room (Autodesk Fusion 360 design; units mm, degrees)
Autodesk Fusion 360 part; units mm, degrees
sketch "Sketch1" plane through (0, 0, 0) normal (0, 1, 0) x (1, 0, 0)
  line L0 (1016, -304.8) -> (-1016, -304.8)
  line L1 (-1016, -304.8) -> (-1016, 304.8)
  line L2 (-1016, 304.8) -> (1016, 304.8)
  line L3 (1016, 304.8) -> (1016, -304.8)
  line L4 (1016, -304.8) -> (-1016, 304.8) construction
  line L5 (-1016, -304.8) -> (1016, 304.8) construction
  line L6 (1016, 304.8) -> (-1016, 304.8)
  line L7 (-1016, 304.8) -> (-1016, 381)
  line L8 (-1016, 381) -> (1016, 381)
  line L9 (1016, 381) -> (1016, 304.8)
  line L10 (1016, 304.8) -> (4064, 304.8)
  line L11 (4064, 304.8) -> (4064, -609.6)
  line L12 (4064, -609.6) -> (1016, -609.6)
  line L13 (1016, -609.6) -> (1016, 304.8)
  line L14 (1016, 381) -> (4064, 381)
  line L15 (4064, 381) -> (4064, 304.8)
  line L16 (4064, 304.8) -> (1016, 304.8)
  line L17 (1016, 304.8) -> (1016, 381)
  dimension "d1" = 2032
  dimension "d2" = 609.6
  dimension "d3" = 76.2
  dimension "d4" = 914.4
  dimension "d5" = 3048
  constraint perpendicular L0 L1
  constraint parallel L0 L2
  constraint parallel L1 L3
  constraint horizontal L0
  constraint coincident L4 origin
  constraint coincident L5 origin
  constraint horizontal L6
  constraint vertical L7
  constraint horizontal L8
  constraint vertical L9
  constraint horizontal L10
  constraint vertical L11
  constraint horizontal L12
  constraint vertical L13
  constraint horizontal L14
  constraint vertical L15
  constraint horizontal L16
  constraint vertical L17
  measures "d1" distance of L1.end L2.end
  measures "d2" distance of L0.end L1.end
  measures "d3" distance of L2.end L8.end
  measures "d4" distance of L2.end L12.end
  measures "d5" distance of L2.end L10.end
extrude "Extrude1" add sketch "Sketch1" along normal blind 5080 contours L2 L6 L7 L8 L9 L17 | L9 L10 L14 L15 L16 L17 makes body 1
extrude "Extrude2" add sketch "Sketch1" along normal blind 914.4 contours L3 L10 L11 L12 L13 L16 bodies 1
sketch "Sketch2" plane through (0, 914.4, 0) normal (0, 1, 0) x (-1, 0, 0)
  line L0 (-4064, 609.6) -> (-4064, -304.8)
  line L1 (-4064, -304.8) -> (-1016, -304.8)
  line L2 (-1016, -304.8) -> (-1016, 609.6)
  line L3 (-1016, 609.6) -> (-4064, 609.6)
  line L4 (-1016, 609.6) -> (-1320.8, 609.6)
  line L5 (-1320.8, 609.6) -> (-1320.8, -304.8)
  line L6 (-1320.8, -304.8) -> (-1016, -304.8)
  line L7 (-1016, -304.8) -> (-1016, 609.6)
  line L8 (-4064, 609.6) -> (-3759.2, 609.6)
  line L9 (-3759.2, 609.6) -> (-3759.2, -304.8)
  line L10 (-3759.2, -304.8) -> (-4064, -304.8)
  line L11 (-4064, -304.8) -> (-4064, 609.6)
  line L12 (-1016, -304.8) -> (-4064, -304.8)
  line L13 (-4064, -304.8) -> (-4064, -101.6)
  line L14 (-4064, -101.6) -> (-1016, -101.6)
  line L15 (-1016, -101.6) -> (-1016, -304.8)
  dimension "d10" = 304.8
  dimension "d11" = 304.8
  dimension "d12" = 203.2
  constraint horizontal L4
  constraint vertical L5
  constraint horizontal L6
  constraint vertical L7
  constraint coincident L2.end L3.start
  constraint horizontal L8
  constraint vertical L9
  constraint horizontal L10
  constraint vertical L11
  constraint coincident L0.start L3.end
  constraint horizontal L12
  constraint vertical L13
  constraint horizontal L14
  constraint vertical L15
  measures "d10" distance of L2.end L4.end
  measures "d11" distance of L0.start L8.end
  measures "d12" distance of L1.end L14.end
extrude "Extrude3" cut sketch "Sketch2" against normal blind 609.6 contours L3 L5 L9 L14 bodies 1
extrude "Extrude4" add sketch "Sketch1" along normal blind 2032 separate body contours L0 L1 L2 L3 L6 L13 makes body 2
sketch "Sketch3" plane through (0, 0, -304.8) normal (0, 0, 1) x (1, 0, 0)
  line L0 (1016, 0) -> (1016, 914.4)
  line L1 (1016, 914.4) -> (4064, 914.4)
  line L2 (4064, 914.4) -> (4064, 5080)
  line L3 (4064, 5080) -> (-1016, 5080)
  line L4 (-1016, 5080) -> (-1016, 0)
  line L5 (-1016, 0) -> (1016, 0)
  line L6 (-1016, 0) -> (76.2, 0)
  line L7 (76.2, 0) -> (76.2, 736.6)
  line L8 (76.2, 736.6) -> (-1016, 736.6)
  line L9 (-1016, 736.6) -> (-1016, 0)
  dimension "d17" = 1092.2
  dimension "d18" = 736.6
  constraint horizontal L6
  constraint vertical L7
  constraint horizontal L8
  constraint vertical L9
  constraint coincident L4.end L5.start
  measures "d17" distance of L4.end L6.end
  measures "d18" distance of L4.end L8.end
extrude "Extrude5" add sketch "Sketch3" along normal blind 685.8 separate body contours L4 L5 L6 L7 L8 L9 makes body 3
sketch "Sketch4" plane through (0, 0, 0) normal (0, -1, 0) x (1, 0, 0)
  line L0 (-1016, -304.8) -> (76.2, -304.8)
  line L1 (76.2, -304.8) -> (76.2, 381)
  line L2 (76.2, 381) -> (-1016, 381)
  line L3 (-1016, 381) -> (-1016, -304.8)
  line L4 (-1016, 381) -> (-889, 381)
  line L5 (-889, 381) -> (-889, 254)
  line L6 (-889, 254) -> (-1016, 254)
  line L7 (-1016, 254) -> (-1016, 381)
  line L8 (-1016, -304.8) -> (-889, -304.8)
  line L9 (-889, -304.8) -> (-889, -177.8)
  line L10 (-889, -177.8) -> (-1016, -177.8)
  line L11 (-1016, -177.8) -> (-1016, -304.8)
  line L12 (76.2, -304.8) -> (-50.8, -304.8)
  line L13 (-50.8, -304.8) -> (-50.8, -177.8)
  line L14 (-50.8, -177.8) -> (76.2, -177.8)
  line L15 (76.2, -177.8) -> (76.2, -304.8)
  line L16 (76.2, 381) -> (-50.8, 381)
  line L17 (-50.8, 381) -> (-50.8, 254)
  line L18 (-50.8, 254) -> (76.2, 254)
  line L19 (76.2, 254) -> (76.2, 381)
  dimension "d21" = 127
  dimension "d22" = 127
  dimension "d23" = 127
  dimension "d24" = 127
  dimension "d25" = 127
  dimension "d26" = 127
  dimension "d27" = 127
  dimension "d28" = 127
  constraint horizontal L4
  constraint vertical L5
  constraint horizontal L6
  constraint vertical L7
  constraint coincident L2.end L3.start
  constraint horizontal L8
  constraint vertical L9
  constraint horizontal L10
  constraint vertical L11
  constraint coincident L0.start L3.end
  constraint horizontal L12
  constraint vertical L13
  constraint horizontal L14
  constraint vertical L15
  constraint coincident L0.end L1.start
  constraint horizontal L16
  constraint vertical L17
  constraint horizontal L18
  constraint vertical L19
  constraint coincident L1.end L2.start
  measures "d21" distance of L2.end L6.end
  measures "d22" distance of L2.end L4.end
  measures "d23" distance of L0.start L10.end
  measures "d24" distance of L0.start L8.end
  measures "d25" distance of L0.end L12.end
  measures "d26" distance of L0.end L14.end
  measures "d27" distance of L1.end L18.end
  measures "d28" distance of L1.end L16.end
extrude "Extrude6" cut sketch "Sketch4" against normal blind 609.6 contours L0 L1 L2 L3 L5 L6 L9 L10 L13 L14 L17 L18 bodies 3
move_body "Move1" bodies 3 to x (1, 0, 0) y (0, 1, 0) z (0, 0, 1) at (939.8, 0, 0)
sketch "Sketch5" plane through (0, 0, 0) normal (0, 1, 0) x (1, 0, 0)
  line L0 (-76.2, 304.8) -> (-914.4, 304.8)
  line L1 (-914.4, 304.8) -> (-914.4, -76.2)
  line L2 (-914.4, -76.2) -> (-76.2, -76.2)
  line L3 (-76.2, -76.2) -> (-76.2, 304.8)
  dimension "d31" = 381
  dimension "d32" = 838.2
  constraint horizontal L0
  constraint vertical L1
  constraint horizontal L2
  constraint vertical L3
  measures "d31" distance of L0.start L2.end
  measures "d32" distance of L0.start L0.end
extrude "Extrude7" add sketch "Sketch5" along normal blind 1879.6 separate body makes body 4
sketch "Sketch6" plane through (0, 0, 76.2) normal (0, 0, 1) x (1, 0, 0)
  line L0 (-914.4, 0) -> (-76.2, 0)
  line L1 (-76.2, 0) -> (-76.2, 1879.6)
  line L2 (-76.2, 1879.6) -> (-914.4, 1879.6)
  line L3 (-914.4, 1879.6) -> (-914.4, 0)
  line L4 (-914.4, 0) -> (-76.2, 0)
  line L5 (-76.2, 0) -> (-76.2, 469.9)
  line L6 (-76.2, 469.9) -> (-914.4, 469.9)
  line L7 (-914.4, 469.9) -> (-914.4, 0)
  line L8 (-914.4, 469.9) -> (-76.2, 469.9)
  line L9 (-76.2, 469.9) -> (-76.2, 939.8)
  line L10 (-76.2, 939.8) -> (-914.4, 939.8)
  line L11 (-914.4, 939.8) -> (-914.4, 469.9)
  line L12 (-914.4, 939.8) -> (-76.2, 939.8)
  line L13 (-76.2, 939.8) -> (-76.2, 1409.7)
  line L14 (-76.2, 1409.7) -> (-914.4, 1409.7)
  line L15 (-914.4, 1409.7) -> (-914.4, 939.8)
  line L16 (-914.4, 1409.7) -> (-76.2, 1409.7)
  line L17 (-76.2, 1409.7) -> (-76.2, 1879.6)
  line L18 (-76.2, 1879.6) -> (-914.4, 1879.6)
  line L19 (-914.4, 1879.6) -> (-914.4, 1409.7)
  line L20 (-914.4, 0) -> (-76.2, 0)
  line L21 (-76.2, 0) -> (-76.2, 234.95)
  line L22 (-76.2, 234.95) -> (-914.4, 234.95)
  line L23 (-914.4, 234.95) -> (-914.4, 0)
  line L24 (-914.4, 1879.6) -> (-76.2, 1879.6)
  line L25 (-76.2, 1879.6) -> (-76.2, 1778)
  line L26 (-76.2, 1778) -> (-914.4, 1778)
  line L27 (-914.4, 1778) -> (-914.4, 1879.6)
  line L28 (-914.4, 1409.7) -> (-76.2, 1409.7)
  line L29 (-76.2, 1409.7) -> (-76.2, 1308.1)
  line L30 (-76.2, 1308.1) -> (-914.4, 1308.1)
  line L31 (-914.4, 1308.1) -> (-914.4, 1409.7)
  line L32 (-914.4, 939.8) -> (-76.2, 939.8)
  line L33 (-76.2, 939.8) -> (-76.2, 838.2)
  line L34 (-76.2, 838.2) -> (-914.4, 838.2)
  line L35 (-914.4, 838.2) -> (-914.4, 939.8)
  line L36 (-914.4, 583.4165) -> (-76.2, 583.4165)
  line L37 (-76.2, 583.4165) -> (-76.2, 469.9)
  line L38 (-76.2, 469.9) -> (-914.4, 469.9)
  line L39 (-914.4, 469.9) -> (-914.4, 583.4165)
  line L40 (-914.4, 234.95) -> (-76.2, 234.95)
  line L41 (-76.2, 234.95) -> (-76.2, 336.55)
  line L42 (-76.2, 336.55) -> (-914.4, 336.55)
  line L43 (-914.4, 336.55) -> (-914.4, 234.95)
  line L44 (-914.4, 0) -> (-863.6, 0)
  line L45 (-863.6, 0) -> (-863.6, 1879.6)
  line L46 (-863.6, 1879.6) -> (-914.4, 1879.6)
  line L47 (-914.4, 1879.6) -> (-914.4, 0)
  line L48 (-76.2, 1879.6) -> (-127, 1879.6)
  line L49 (-127, 1879.6) -> (-127, 2.6787)
  line L50 (-127, 2.6787) -> (-76.2, 2.6787)
  line L51 (-76.2, 2.6787) -> (-76.2, 1879.6)
  dimension "d35" = 469.9
  dimension "d36" = 469.9
  dimension "d37" = 469.9
  dimension "d38" = 838.2
  dimension "d39" = 101.6
  dimension "d40" = 101.6
  dimension "d41" = 101.6
  dimension "d42" = 50.8
  dimension "d43" = 50.8
  constraint horizontal L4
  constraint vertical L5
  constraint horizontal L6
  constraint vertical L7
  constraint coincident L0.start L3.end
  constraint horizontal L8
  constraint vertical L9
  constraint horizontal L10
  constraint vertical L11
  constraint horizontal L12
  constraint vertical L13
  constraint horizontal L14
  constraint vertical L15
  constraint horizontal L16
  constraint vertical L17
  constraint horizontal L18
  constraint vertical L19
  constraint coincident L1.end L2.start
  constraint horizontal L20
  constraint vertical L21
  constraint horizontal L22
  constraint vertical L23
  constraint midpoint L5 L21.end
  constraint horizontal L24
  constraint vertical L25
  constraint horizontal L26
  constraint vertical L27
  constraint coincident L17 L25.end
  constraint horizontal L28
  constraint vertical L29
  constraint horizontal L30
  constraint vertical L31
  constraint horizontal L32
  constraint vertical L33
  constraint horizontal L34
  constraint vertical L35
  constraint horizontal L36
  constraint vertical L37
  constraint horizontal L38
  constraint vertical L39
  constraint coincident L11 L36.start
  constraint horizontal L40
  constraint vertical L41
  constraint horizontal L42
  constraint vertical L43
  constraint horizontal L44
  constraint vertical L45
  constraint horizontal L46
  constraint vertical L47
  constraint horizontal L48
  constraint vertical L49
  constraint horizontal L50
  constraint vertical L51
  measures "d35" distance of L0.start L6.end
  measures "d36" distance of L6.end L10.end
  measures "d37" distance of L10.end L14.end
  measures "d38" distance of L10.end L9.end
  measures "d39" distance of L14.end L30.end
  measures "d40" distance of L10.end L34.end
  measures "d41" distance of L22.end L42.end
  measures "d42" distance of L0.start L44.end
  measures "d43" distance of L1.end L48.end
extrude "Extrude8" cut sketch "Sketch6" against normal blind 381 contours L0 L1 L4 L5 L20 L21 L22 L40 L45 L49 L50 | L6 L8 L38 L42 L45 L49 | L34 L36 L45 L49 | L10 L12 L30 L32 L45 L49 | L14 L16 L26 L28 L45 L49 bodies 4
sketch "Sketch7" plane through (0, 0, 0) normal (0, 1, 0) x (1, 0, 0)
  line L0 (431.8, -1066.8) -> (-177.8, -1066.8)
  line L1 (-177.8, -1066.8) -> (-177.8, -457.2)
  line L2 (-177.8, -457.2) -> (431.8, -457.2)
  line L3 (431.8, -457.2) -> (431.8, -1066.8)
  line L4 (431.8, -1066.8) -> (-177.8, -457.2) construction
  line L5 (-177.8, -1066.8) -> (431.8, -457.2) construction
  point P0 (127, -762)
  dimension "d46" = 609.6
  dimension "d47" = 609.6
  constraint perpendicular L0 L1
  constraint parallel L0 L2
  constraint parallel L1 L3
  constraint horizontal L0
  constraint coincident L4 P0
  constraint coincident L5 P0
  measures "d46" distance of L1.end L2.end
  measures "d47" distance of L0.end L1.end
extrude "Extrude9" add sketch "Sketch7" along normal blind 1778 separate body makes body 5
extrude "Extrude10" add 1 faces at (228.6, 1778, 863.6) along direction (0, 1, 0) blind 152.4 on bodies 5 bodies 5
extrude "Extrude11" cut 1 faces at (228.6, 1930.4, 863.6) along direction (0, -1, 0) blind 304.8 on bodies 5 bodies 5
hidden bodies 2 5
